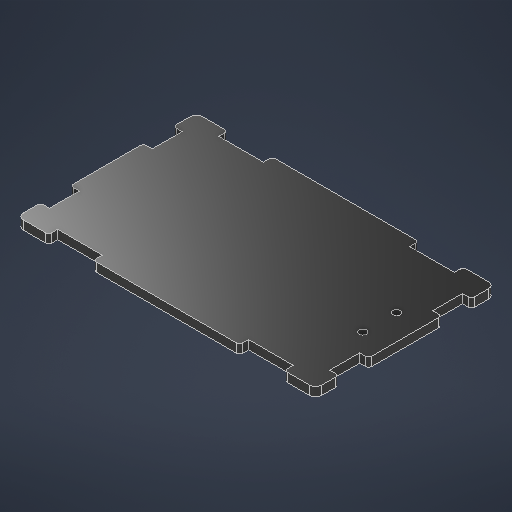
# Autodesk Inventor part: TransmitterCeil
Saved by Autodesk Inventor 2027.1 (Build 311270010, 270A)
## iProperties
Created: 2026-10-18
Part Number: TransmitterCeil
Material: MDF Medium Density Fiberboard
Document SubType Name: Modeling
Designer: SDS Scholar
Density: 0.8 g/cm^3
Appearance: Glossy - Black
Mass: 14.936 g
Surface Area: 137.589 cm^2
Volume: 18.6699 cm^3
Author: SDS Scholar
Autodesk Inventor part; units mm, degrees
ref_plane "YZ Plane" through (0, 0, 0) normal (1, 0, 0) x (0, 1, 0)
ref_plane "XZ Plane" through (0, 0, 0) normal (0, 1, 0) x (-1, 0, 0)
ref_plane "XY Plane" through (0, 0, 0) normal (0, 0, 1) x (1, 0, 0)
sketch "Sketch1" plane through (0, 0, 0) normal (0, 1, 0) x (-1, 0, 0)
  line L0 (50, 27) -> (-50, 27)
  line L1 (-50, 27) -> (-50, -27)
  line L2 (-50, -27) -> (50, -27)
  line L3 (50, -27) -> (50, 27)
  circle A0 centre (-41.5, -5.66) radius 1.25
  line L4 (50, 0) -> (-50, 0) construction
  circle A1 centre (-41.5, 5.66) radius 1.25
  line L5 (-50, -27) -> (50, -27)
  line L6 (50, -27) -> (50, -30)
  line L7 (50, -30) -> (-50, -30)
  line L8 (-50, -30) -> (-50, -27)
  line L9 (47, -22.25) -> (50, -22.25)
  line L10 (50, -22.25) -> (50, -12.25)
  line L11 (50, -12.25) -> (47, -12.25)
  line L12 (47, -12.25) -> (47, -22.25)
  line L13 (-50, -12.25) -> (-47, -12.25)
  line L14 (-47, -12.25) -> (-47, -22.25)
  line L15 (-47, -22.25) -> (-50, -22.25)
  line L16 (-50, -22.25) -> (-50, -12.25)
  line L17 (47, -27) -> (47, 0) construction
  line L18 (-39.5, -30) -> (-24.5, -30)
  line L19 (-24.5, -30) -> (-24.5, -27)
  line L20 (-24.5, -27) -> (-39.5, -27)
  line L21 (-39.5, -27) -> (-39.5, -30)
  line L22 (0, -30) -> (0, 27) construction
  line L23 (24.5, -30) -> (24.5, -27)
  line L24 (39.5, -27) -> (39.5, -30)
  line L25 (50, 27) -> (50, 30)
  line L26 (50, 30) -> (-50, 30)
  line L27 (-50, 30) -> (-50, 27)
  line L28 (47, 22.25) -> (50, 22.25)
  line L29 (50, 12.25) -> (47, 12.25)
  line L30 (47, 12.25) -> (47, 22.25)
  line L31 (-47, 12.25) -> (-47, 22.25)
  line L32 (-50, 12.25) -> (-47, 12.25)
  line L33 (-47, 22.25) -> (-50, 22.25)
  line L34 (-24.5, 30) -> (-24.5, 27)
  line L35 (-39.5, 27) -> (-39.5, 30)
  line L36 (24.5, 30) -> (24.5, 27)
  line L37 (39.5, 27) -> (39.5, 30)
  line L38 (-50, -7.5) -> (-47, -7.5)
  line L39 (-47, -7.5) -> (-47, 7.5)
  line L40 (-47, 7.5) -> (-50, 7.5)
  line L41 (-50, 7.5) -> (-50, -7.5)
  line L42 (-47, -7.5) -> (-47, -27) construction
  point P0 (0, 0)
  point P1 (0, -27)
  point P2 (-32, -30)
  point P3 (-39.5, -30)
  point P4 (-39.5, -27)
  point P5 (-24.5, -27)
  point P6 (-24.5, -30)
  point P7 (24.5, -30)
  point P8 (24.5, -27)
  point P9 (39.5, -27)
  point P10 (39.5, -30)
  point P11 (50, -22.25)
  point P12 (50, -12.25)
  point P13 (50, 12.25)
  point P14 (50, 22.25)
  point P15 (39.5, 30)
  point P16 (39.5, 27)
  point P17 (24.5, 27)
  point P18 (24.5, 30)
  point P19 (-24.5, 30)
  point P20 (-24.5, 27)
  point P21 (-39.5, 27)
  point P22 (-39.5, 30)
  point P23 (-47, 0)
  point P24 (0, 0)
  point P25 (-47, -17.25)
  point P26 (47, -17.25)
  dimension "d0" = 54
  dimension "d1" = 100
  dimension "d27" = 2.5
  dimension "d29" = 8.5
  dimension "d30" = 11.32
  dimension "d33" = 3
  dimension "d34" = 10
  dimension "d35" = 3
  dimension "d36" = 10
  dimension "d37" = 3
  dimension "d39" = 3
  dimension "d42" = 3
  dimension "d43" = 15
  dimension "d44" = 18
  dimension "d45" = 15
  dimension "d46" = 3
  constraints: 86 end point, 23 symmetric about line, 12 parallel, 11 midpoint, 8 perpendicular, 6 horizontal, 6 point on line, 3 horizontal alignment, 2 centre point, 1 vertical alignment, 1 other
  measures "d0" distance of L0.end L1.end
  measures "d1" distance of L1.end L2.end
  measures "d27" diameter of A0
  measures "d29" distance from line of L1 A0.centre
  measures "d30" distance of A1.centre A0.centre
  measures "d33" distance of L2.end L6.end
  measures "d34" distance of L11.end L9.start
  measures "d35" distance of L10.end L11.end
  measures "d36" distance of L15.end L13.start
  measures "d37" distance of L14.end L15.end
  measures "d39" distance between parallel lines of L17 L3
  measures "d42" distance of L18.end L19.end
  measures "d43" distance of L18.start L18.end
  measures "d44" distance from line of L8 point (-32, -30)
  measures "d45" distance of L38.end L39.end
  measures "d46" distance of L38.start L38.end
extrude "Extrusion1" add sketch "Sketch1" along normal blind 3 contours L3 L28 L30 L29 L11 L12 L9 L2 L1 L15 L14 L13 L38 L39 L40 L32 L31 L33 L0 | L0 L37 L26 L25 | L0 L34 L26 L36 | L0 L27 L26 L35 | L6 L7 L24 L2 | L23 L7 L19 L2 | L40 L39 L38 L1 | L21 L7 L8 L2
fillet "Fillet3" radius 1 16 edges at (24.5, 1.5, 30) (39.5, 1.5, 30) (50, 1.5, 22.25) (50, 1.5, 12.25) (50, 1.5, -12.25) (50, 1.5, -22.25) (-24.5, 1.5, 30) (-39.5, 1.5, 30) (-50, 1.5, 22.25) (-50, 1.5, 12.25) (-50, 1.5, -12.25) (-50, 1.5, -22.25) (-39.5, 1.5, -30) (-24.5, 1.5, -30) (24.5, 1.5, -30) (39.5, 1.5, -30)
fillet "Fillet4" radius 2 4 edges at (-50, 1.5, -30) (-50, 1.5, 30) (50, 1.5, -30) (50, 1.5, 30)
equation "\"d1\" = TransmitterAreaWidth"
equation "\"GridProcutClearance\" = 5"
equation "\"GridBorderThickness\" = 5"
equation "\"GridBorderFillets\" = 7"
equation "\"GridTotalSize\" = 65"
equation "\"GridRobotClearance\" = 65"
equation "\"AluminiumExtrusionClearance\" = 35"
equation "\"BaseTotalLength\" = 885"
equation "\"WorkspaceLength\" = 515"
equation "\"WorkspaceHeight\" = 183"
equation "\"AxesBaseFillet\" = 15"
equation "\"Zaxis\" = 197"
equation "\"ProductTotalHeight\" = 45"
equation "\"VerticalStroke\" = 105"
equation "\"BackArea\" = 165"
equation "\"CylinderStroke\" = 75"
equation "\"BoxesWidth\" = 125"
equation "\"BaseWoodThickness\" = 7"
equation "\"Kerf\" = 0.3"
equation "\"TransmitterAreaWidth\" = 100"
equation "\"RxThickness\" = 1.8"
equation "\"support_2\" = 265"
body "Solid1"
